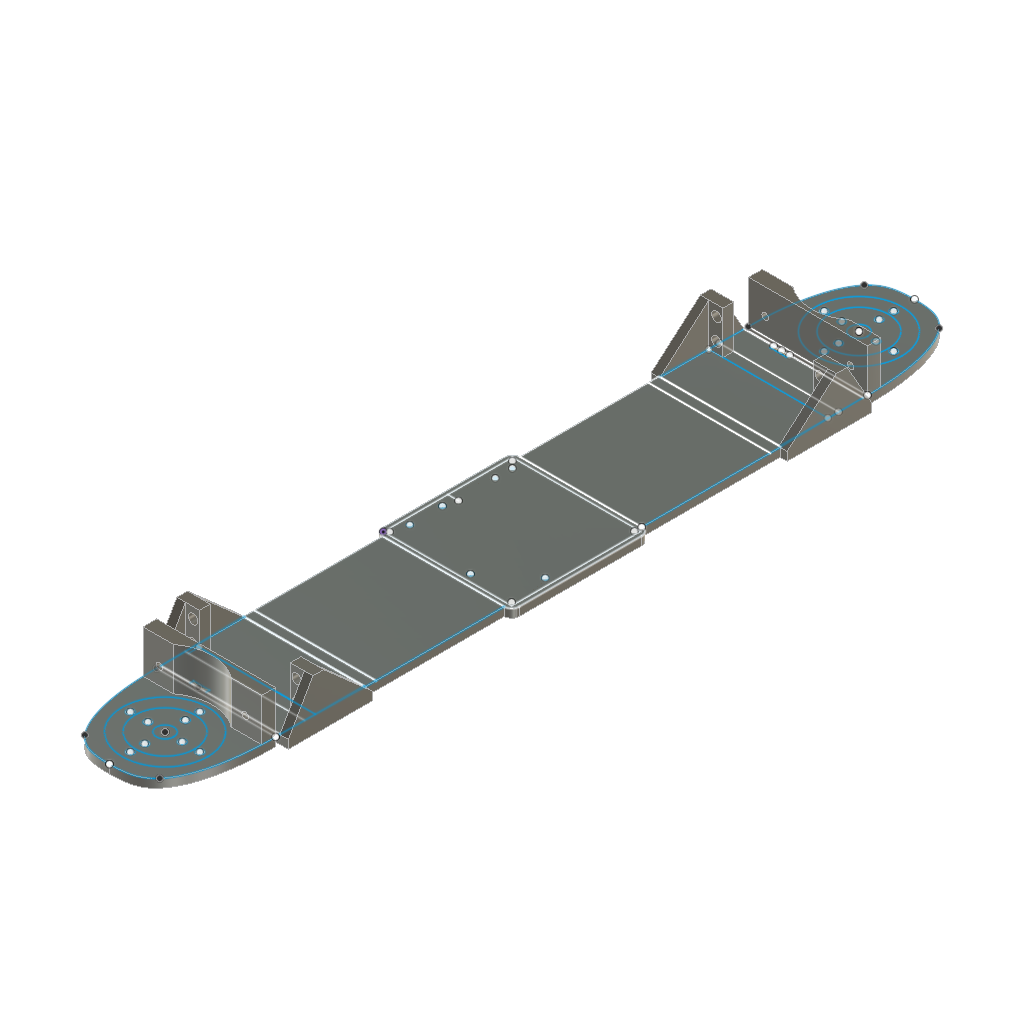
Aircraft Skeleton (Autodesk Fusion 360 design; units mm, degrees)
Autodesk Fusion 360 part; units mm, degrees
sketch "Sketch1" plane through (0, 0, 0) normal (0, 0, 1) x (1, 0, 0)
  line L0 (0, 0) -> (60, 0)
  line L1 (60, 0) -> (60, 60.328)
  line L2 (60, 60.328) -> (0, 60.328)
  line L3 (0, 60.328) -> (0, 0)
  circle A0 centre (4.445, 55.8804) radius 0.5
  circle A1 centre (4.445, 47.8804) radius 0.5
  circle A2 centre (3.398, 9) radius 1
  circle A3 centre (3.398, 24.24) radius 1
  circle A4 centre (37.45, 3.305) radius 1
  circle A5 centre (56.5, 19.18) radius 1
  line L4 (58.5, 62.328) -> (1.5, 62.328)
  line L5 (-2, 58.828) -> (-2, 1.5)
  line L6 (1.5, -2) -> (58.5, -2)
  line L7 (62, 1.5) -> (62, 58.828)
  arc A6 (1.5, 62.328) -> (-2, 58.828) centre (1.5, 58.828) ccw
  arc A7 (62, 58.828) -> (58.5, 62.328) centre (58.5, 58.828) ccw
  arc A8 (58.5, -2) -> (62, 1.5) centre (58.5, 1.5) ccw
  arc A9 (-2, 1.5) -> (1.5, -2) centre (1.5, 1.5) ccw
  line L8 (1.5, -2) -> (58.5, -2)
  line L9 (58.5, -2) -> (58.5, -62)
  line L10 (58.5, -62) -> (1.5, -62)
  line L11 (1.5, -62) -> (1.5, -2)
  line L12 (1.5, -62) -> (58.5, -62)
  line L13 (58.5, -62) -> (58.5, -67)
  line L14 (58.5, -67) -> (1.5, -67)
  line L15 (1.5, -67) -> (1.5, -62)
  line L16 (1.5, -67) -> (58.5, -67)
  line L17 (57.8, -106.2) -> (2.2, -106.2)
  line L18 (57.8, -94.7) -> (2.2, -94.7)
  line L19 (57.8, -67) -> (2.2, -67)
  line L20 (2.2, -67) -> (2.2, -106.2)
  line L21 (2.2, -106.2) -> (57.8, -106.2)
  line L22 (57.8, -106.2) -> (57.8, -67)
  line L23 (57.8, -106.2) -> (58.5, -67)
  line L24 (1.5, -67) -> (2.2, -106.2)
  line L25 (2.2, -108.2) -> (57.8, -108.2)
  circle A10 centre (30, -132.05) radius 13.85
  circle A11 centre (30, -122.55) radius 1.5
  circle A12 centre (38, -132.05) radius 1.5
  circle A13 centre (22, -132.05) radius 1.5
  circle A14 centre (30, -141.55) radius 1.5
  circle A15 centre (30, -132.05) radius 4
  circle A16 centre (30, -115.8) radius 1.5
  circle A17 centre (30, -148.3) radius 1.5
  circle A18 centre (13.75, -132.05) radius 1.5
  circle A19 centre (46.25, -132.05) radius 1.5
  circle A20 centre (30, -132.05) radius 20
  spline S0 degree 5 poles (2.2, -108.2) (2.2, -110.2358) (2.2593, -114.2119) (2.526, -119.8896) (3.2303, -126.8958) (4.6648, -134.7271) (6.6317, -141.619) (9.1298, -147.4803) (12.1699, -152.1961) (15.8043, -155.4644) (20.0344, -157.2387) (23.8195, -157.8281) (26.8436, -158.0092) (28.9353, -158.0498) (30, -158.05) knots 0 0 0 0 0 0 0.1 0.2 0.3 0.4 0.5 0.6 0.7 0.8 0.9 1 1 1 1 1 1
  line L26 (22.2675, -158.0488) -> (37.7325, -158.0512)
  line L27 (9, -148) -> (16, -156.1)
  line L28 (2.2, -98.7565) -> (2.2, -117.6435)
  spline S1 degree 5 poles (57.8, -108.2) (57.8, -110.2358) (57.7407, -114.2119) (57.474, -119.8896) (56.7697, -126.8958) (55.3352, -134.7271) (53.3683, -141.619) (50.8702, -147.4803) (47.8301, -152.1961) (44.1957, -155.4644) (39.9656, -157.2387) (36.1805, -157.8281) (33.1564, -158.0092) (31.0647, -158.0498) (30, -158.05) knots 0 0 0 0 0 0 0.1 0.2 0.3 0.4 0.5 0.6 0.7 0.8 0.9 1 1 1 1 1 1
  line L29 (57.8, -98.7565) -> (57.8, -117.6435)
  line L30 (51, -148) -> (44, -156.1)
  line L31 (37.7325, -158.0488) -> (22.2675, -158.0512)
  line L32 (2.2, -106.2) -> (19.7, -106.2)
  line L33 (23.45, -104.7) -> (15.95, -104.7)
  line L34 (15.95, -104.7) -> (15.95, -106.2)
  line L35 (23.45, -106.2) -> (23.45, -104.7)
  line L36 (23.45, -104.7) -> (19.7, -106.2) construction
  line L37 (15.95, -104.7) -> (19.7, -106.2) construction
  line L38 (0, 30.164) -> (5, 30.164)
  line L39 (1.5, 62.328) -> (58.5, 62.328)
  line L40 (58.5, 122.328) -> (1.5, 122.328)
  line L41 (1.5, 122.328) -> (58.5, 122.328)
  line L42 (58.5, 62.328) -> (58.5, 122.328)
  line L43 (57.8, 127.328) -> (2.2, 127.328)
  line L44 (23.45, 166.528) -> (23.45, 165.028)
  line L45 (15.95, 165.028) -> (19.7, 166.528) construction
  line L46 (2.2, 166.528) -> (57.8, 166.528)
  line L47 (57.8, 166.528) -> (2.2, 166.528)
  line L48 (15.95, 165.028) -> (15.95, 166.528)
  line L49 (23.45, 165.028) -> (19.7, 166.528) construction
  line L50 (23.45, 165.028) -> (15.95, 165.028)
  line L51 (2.2, 166.528) -> (19.7, 166.528)
  line L52 (57.8, 155.028) -> (2.2, 155.028)
  circle A21 centre (38, 192.378) radius 1.5
  circle A22 centre (46.25, 192.378) radius 1.5
  circle A23 centre (22, 192.378) radius 1.5
  circle A24 centre (13.75, 192.378) radius 1.5
  spline S2 degree 5 poles (2.2, 168.528) (2.2, 170.5638) (2.2593, 174.5399) (2.526, 180.2176) (3.2303, 187.2238) (4.6648, 195.0551) (6.6317, 201.947) (9.1298, 207.8083) (12.1699, 212.5241) (15.8043, 215.7924) (20.0344, 217.5667) (23.8195, 218.1561) (26.8436, 218.3372) (28.9353, 218.3778) (30, 218.378) knots 0 0 0 0 0 0 0.1 0.2 0.3 0.4 0.5 0.6 0.7 0.8 0.9 1 1 1 1 1 1
  line L53 (2.2, 159.0845) -> (2.2, 177.9715)
  line L54 (9, 208.328) -> (16, 216.428)
  line L55 (22.2675, 218.3768) -> (37.7325, 218.3792)
  circle A25 centre (30, 192.378) radius 13.85
  line L56 (2.2, 168.528) -> (57.8, 168.528)
  circle A26 centre (30, 201.878) radius 1.5
  circle A27 centre (30, 192.378) radius 20
  circle A28 centre (30, 208.628) radius 1.5
  spline S3 degree 5 poles (57.8, 168.528) (57.8, 170.5638) (57.7407, 174.5399) (57.474, 180.2176) (56.7697, 187.2238) (55.3352, 195.0551) (53.3683, 201.947) (50.8702, 207.8083) (47.8301, 212.5241) (44.1957, 215.7924) (39.9656, 217.5667) (36.1805, 218.1561) (33.1564, 218.3372) (31.0647, 218.3778) (30, 218.378) knots 0 0 0 0 0 0 0.1 0.2 0.3 0.4 0.5 0.6 0.7 0.8 0.9 1 1 1 1 1 1
  line L57 (57.8, 159.0845) -> (57.8, 177.9715)
  line L58 (51, 208.328) -> (44, 216.428)
  line L59 (37.7325, 218.3768) -> (22.2675, 218.3792)
  circle A29 centre (30, 182.878) radius 1.5
  circle A30 centre (30, 192.378) radius 4
  line L60 (1.5, 127.328) -> (1.5, 122.328)
  line L61 (1.5, 127.328) -> (58.5, 127.328)
  line L62 (58.5, 122.328) -> (58.5, 127.328)
  line L63 (1.5, 122.328) -> (1.5, 62.328)
  line L64 (58.5, 127.328) -> (1.5, 127.328)
  circle A31 centre (30, 176.128) radius 1.5
  line L65 (57.8, 166.528) -> (57.8, 127.328)
  line L66 (1.5, 127.328) -> (2.2, 166.528)
  line L67 (2.2, 127.328) -> (2.2, 166.528)
  line L68 (57.8, 166.528) -> (58.5, 127.328)
  line L69 (3.6, -94.7) -> (3.6, -89.7)
  line L70 (2.2, -89.7) -> (57.8, -89.7)
  line L71 (57.8, -89.7) -> (57.8, -89.7)
  line L72 (57.8, -89.7) -> (2.2, -89.7)
  line L73 (2.2, -89.7) -> (2.2, -89.7)
  line L74 (2.2, 150.028) -> (57.8, 150.028)
  point P0 (30, -132.05)
  point P1 (30, -132.05)
  point P2 (30, -132.05)
  point P3 (30, -132.05)
  point P4 (12.5, -152.05)
  point P5 (47.5, -152.05)
  point P6 (19.7, -106.2)
  point P7 (47.5, 212.378)
  point P8 (30, 192.378)
  point P9 (30, 192.378)
  point P10 (30, 192.378)
  point P11 (30, 192.378)
  point P12 (19.7, 166.528)
  point P13 (12.5, 212.378)
  dimension "d1" = 60
  dimension "d2" = 60.328
  dimension "d5" = 1
  dimension "d6" = 8
  dimension "d7" = 1
  dimension "d10" = 2
  dimension "d11" = 15.24
  dimension "d12" = 2
  dimension "d15" = 2
  dimension "d18" = 2
  dimension "d20" = 2
  dimension "d21" = 2
  dimension "d22" = 2
  dimension "d23" = 2
  dimension "d24" = 3.5
  dimension "d25" = 60
  dimension "d26" = 5
  dimension "d29" = 55.6
  dimension "d30" = 39.2
  dimension "d31" = 11.5
  dimension "d32" = 27.7
  dimension "d33" = 2
  dimension "d36" = 16
  dimension "d37" = 19
  dimension "d38" = 3
  dimension "d39" = 3
  dimension "d40" = 3
  dimension "d41" = 3
  dimension "d42" = 8
  dimension "d43" = 32.5
  dimension "d44" = 3
  dimension "d45" = 3
  dimension "d46" = 32.5
  dimension "d47" = 3
  dimension "d48" = 3
  dimension "d49" = 40
  dimension "d52" = 17.5
  dimension "d59" = 5
  constraint horizontal L0
  constraint vertical L1
  constraint horizontal L2
  constraint vertical L3
  constraint coincident L0.start L3.end
  constraint tangent L4 A6
  constraint tangent L5 A6
  constraint tangent L4 A7
  constraint tangent L7 A7
  constraint equal A6 A7
  constraint tangent L6 A8
  constraint tangent L7 A8
  constraint equal A6 A8
  constraint tangent L5 A9
  constraint tangent L6 A9
  constraint equal A6 A9
  constraint horizontal L8
  constraint vertical L9
  constraint horizontal L10
  constraint vertical L11
  constraint horizontal L12
  constraint vertical L13
  constraint horizontal L14
  constraint vertical L15
  constraint horizontal L16
  constraint horizontal L17
  constraint horizontal L19
  constraint perpendicular L19 L20
  constraint parallel L19 L21
  constraint parallel L20 L22
  constraint coincident L22 L18.start
  constraint coincident L20 L18.end
  constraint coincident P3 P2
  constraint concentric A10 A15
  constraint midpoint S0.end L26
  constraint midpoint P4 L27
  constraint midpoint L25.start L28
  constraint perpendicular L20 L32
  constraint horizontal L33
  constraint perpendicular L33 L34
  constraint parallel L34 L35
  constraint coincident L36 P6
  constraint coincident L37 P6
  constraint coincident P6 L32.end
  constraint coincident L17 L34.end
  constraint coincident L17 L35.start
  constraint midpoint L3 L38.start
  constraint perpendicular L3 L38
  constraint symmetric L6.end L38 L4.start
  constraint symmetric L6.start L38 L4.end
  constraint symmetric L9.end L38 L40.start
  constraint symmetric L10.end L38 L40.end
  constraint symmetric L13.end L38 L61.end
  constraint symmetric L14.end L38 L60.start
  constraint symmetric L19.start L38 L43.start
  constraint symmetric L19.end L38 L43.end
  constraint symmetric L17.end L38 L46.start
  constraint symmetric L17.start L38 L46.end
  constraint symmetric L18.start L38 L52.start
  constraint symmetric L18.end L38 L52.end
  constraint symmetric L25.start L38 S2.start
  constraint symmetric L25.end L38 L56.end
  constraint symmetric A10 L38 A25
  constraint symmetric P3 L38 P11
  constraint symmetric A11 L38 A29
  constraint symmetric A12 L38 A21
  constraint symmetric A13 L38 A23
  constraint symmetric A14 L38 A26
  constraint symmetric A15 L38 A30
  constraint symmetric A16 L38 A31
  constraint symmetric A17 L38 A28
  constraint symmetric A18 L38 A24
  constraint symmetric A19 L38 A22
  constraint symmetric A20 L38 A27
  constraint symmetric P4 L38 P13
  constraint symmetric S0.end L38 S2.end
  constraint symmetric L26.start L38 L55.start
  constraint symmetric L26.end L38 L55.end
  constraint symmetric L27.start L38 L54.start
  constraint symmetric L27.end L38 L54.end
  constraint symmetric L28.start L38 L53.start
  constraint symmetric L28.end L38 L53.end
  constraint symmetric P5 L38 P7
  constraint symmetric L29.start L38 L57.start
  constraint symmetric L29.end L38 L57.end
  constraint symmetric L30.start L38 L58.start
  constraint symmetric L30.end L38 L58.end
  constraint symmetric L31.start L38 L59.start
  constraint symmetric L31.end L38 L59.end
  constraint symmetric P6 L38 P12
  constraint symmetric L33.start L38 L44.end
  constraint symmetric L33.end L38 L45.start
  constraint symmetric L34.end L38 L48.end
  constraint symmetric L35.start L38 L44.start
  constraint coincident L18 L69.start
  constraint perpendicular L18 L69
  constraint horizontal L70
  constraint horizontal L72
  constraint coincident L22 L70.end
  constraint coincident L20 L70.start
  constraint symmetric L38 L70.start L74.start
  constraint symmetric L38 L70.end L74.end
  measures "d1" distance of L0.start L0.end
  measures "d2" distance of L0.start L2.end
  measures "d5" diameter of A0
  measures "d6" distance of A0.centre A1.centre
  measures "d7" diameter of A1
  measures "d10" diameter of A2
  measures "d11" distance of A2.centre A3.centre
  measures "d12" diameter of A3
  measures "d15" diameter of A4
  measures "d18" diameter of A5
  measures "d20" distance of L2 L4
  measures "d21" distance of L3 L5
  measures "d22" distance of L0 L6
  measures "d23" distance of L1 L7
  measures "d24" radius of A6
  measures "d25" distance of L6.start L10.end
  measures "d26" distance of L10.end L14.end
  measures "d29" distance of L17.end L17.start
  measures "d30" distance of L19.end L17.end
  measures "d31" distance of L17 L18
  measures "d32" distance of L16 L18
  measures "d36" distance of A12.centre A13.centre
  measures "d37" distance of A11.centre A14.centre
  measures "d38" diameter of A11
  measures "d39" diameter of A12
  measures "d40" diameter of A13
  measures "d41" diameter of A14
  measures "d42" diameter of A15
  measures "d43" distance of A16.centre A17.centre
  measures "d44" diameter of A16
  measures "d45" diameter of A17
  measures "d46" distance of A18.centre A19.centre
  measures "d47" diameter of A18
  measures "d48" diameter of A19
  measures "d49" diameter of A20
  measures "d52" distance of L17.end P6
  measures "d59" distance of L69.start L69.end
extrude "Extrude1" add sketch "Sketch1" against normal blind 4 contours L0 L1 L2 L3 | A0 | A1 | A2 | A3 | A4 | A5 | L4 L5 L6 L7 A6 A7 A8 A9 L8 L39 | L4 L39 L40 L41 L42 L63 | L40 L41 L43 L60 L61 L62 L64 | L57 L61 L64 L65 L68 | L53 L61 L64 L66 L67 | L6 L8 L9 L10 L11 L12 | L43 L61 L64 L65 L67 L74 | L44 L46 L47 L48 L50 L51 L52 L53 L57 L65 L67 | L10 L12 L13 L14 L15 L16 L19 | L52 L65 L67 L74 | L44 L46 L47 L48 L50 L51 | S2 L56 S3 | L14 L16 L22 L23 L29 | L14 L16 L20 L24 L28 | L14 L16 L19 L20 L22 L70 L72 | L17 L18 L20 L21 L22 L28 L29 L32 L33 L34 L35 | L18 L22 L69 L70 L72 | L17 L21 L32 L33 L34 L35 | L25 S0 S1 | L18 L20 L69 L70 L72 | A10 | A11 | A12 | A13 | A14 | A15 | A16 | A17 | A18 | A19 | A20 | A21 | A22 | A23 | A24 | A25 | A26 | A27 | A28 | A29 | A30 | A31 makes body 1 at (38.8701, 174.7326, 0) makes body 2 at (38.8701, -114.4046, 0) makes body 3 at (20.5, -43.6667, 0)
extrude "Extrude2" cut sketch "Sketch1" against normal blind 13 contours A2 | A3 | A4 | A5 | A11 | A12 | A13 | A14 | A16 | A17 | A18 | A19 | A21 | A22 | A23 | A24 | A26 | A28 | A29 | A31 bodies 1 2 3
extrude "Extrude3" add sketch "Sketch1" along normal blind 20 contours L52 L65 L67 L74 | L18 L22 L69 L70 L72 | L18 L20 L69 L70 L72 bodies 3
sketch "Sketch2" plane through (0, -94.7, 0) normal (0, -1, 0) x (1, 0, 0)
  line L0 (2.2, 0) -> (57.8, 0)
  line L1 (57.8, 0) -> (57.8, 20)
  line L2 (57.8, 20) -> (2.2, 20)
  line L3 (2.2, 20) -> (2.2, 0)
  line L4 (54.25, 20) -> (5.75, 20)
  circle A0 centre (5.75, 15) radius 2.25
  circle A1 centre (5.75, 5) radius 2.25
  line L5 (30, 20) -> (30, 19.5)
  circle A2 centre (54.25, 15) radius 2.25
  circle A3 centre (54.25, 5) radius 2.25
  line L6 (51.25, 20) -> (8.75, 20)
  line L7 (8.75, 20) -> (8.75, 0)
  line L8 (51.25, 20) -> (51.25, 0)
  line L9 (8.75, 0) -> (51.25, 0)
  point P0 (30, 20)
  point P1 (5.75, 10)
  dimension "d62" = 48.5
  dimension "d65" = 10
  dimension "d66" = 4.5
  dimension "d67" = 4.5
  dimension "d68" = 42.5
  constraint midpoint L4 P0
  constraint coincident L2 P0
  constraint parallel L2 L4
  constraint coincident P0 L5.start
  constraint perpendicular L4 L5
  constraint symmetric A0 L5 A2
  constraint symmetric A1 L5 A3
  constraint midpoint P0 L6
  constraint coincident L4 L6.end
  constraint coincident L0 L7.end
  constraint perpendicular L0 L7
  constraint coincident L0 L8.end
  constraint perpendicular L0 L8
  measures "d62" distance of L4.start L4.end
  measures "d65" distance of A0.centre A1.centre
  measures "d66" diameter of A0
  measures "d67" diameter of A1
  measures "d68" distance of L6.start L6.end
extrude "Extrude4" cut sketch "Sketch2" against normal blind 350 contours L0 L2 L4 L6 L7 L8 L9 | A0 | A1 | A2 | A3 bodies 3
sketch "Sketch3" plane through (2.2, 0, 0) normal (-1, 0, 0) x (0, -1, 0)
  line L0 (89.7, 0) -> (94.7, 0)
  line L1 (94.7, 0) -> (94.7, 20)
  line L2 (94.7, 20) -> (89.7, 20)
  line L3 (89.7, 20) -> (89.7, 0)
  line L4 (89.7, 20) -> (67, 0)
  line L5 (67, 0) -> (67, -4)
  line L6 (67, -4) -> (94.7, -4)
  line L7 (94.7, -4) -> (94.7, 20)
  line L8 (89.7, 20) -> (94.7, 20)
  line L9 (94.7, 20) -> (106.2, 0)
  line L10 (106.2, 0) -> (106.2, -4)
  line L11 (106.2, -4) -> (94.7, -4)
  constraint coincident L2.end L3.start
  constraint perpendicular L2 L5
  constraint perpendicular L1 L6
  constraint coincident L1.end L2.start
  constraint perpendicular L2 L7
  constraint perpendicular L8 L10
  constraint perpendicular L7 L11
extrude "Extrude5" add sketch "Sketch3" along normal blind 4 bodies 3
move_body "Move1" bodies 3 to x (1, 0, 0) y (0, 1, 0) z (0, 0, 1) at (-49.05, 0, 0)
move_body "Move2" bodies 3 to x (1, 0, 0) y (0, 1, 0) z (0, 0, 1) at (-6.55, 0, 0)
extrude "Extrude6" add sketch "Sketch3" against normal blind 4 bodies 3
move_body "Move3" bodies 3 to x (1, 0, 0) y (0, 1, 0) z (0, 0, 1) at (-10, 0, 0)
move_body "Move4" bodies 3 to x (1, 0, 0) y (0, 1, 0) z (0, 0, 1) at (65.6, 0, 0)
sketch "Sketch4" plane through (57.8, 0, 0) normal (1, 0, 0) x (0, 1, 0)
  line L0 (150.028, 0) -> (155.028, 0)
  line L1 (155.028, 0) -> (155.028, 20)
  line L2 (155.028, 20) -> (150.028, 20)
  line L3 (150.028, 20) -> (150.028, 0)
  line L4 (150.028, 20) -> (155.028, 20)
  line L5 (155.028, 20) -> (166.5, 0)
  line L6 (166.5, 0) -> (166.5, -4)
  line L7 (166.5, -4) -> (150.028, -4)
  line L8 (150.028, 20) -> (127, 0)
  line L9 (127, 0) -> (127, -4)
  line L10 (127, -4) -> (150.028, -4)
  constraint coincident L2.end L3.start
  constraint coincident L1.end L2.start
  constraint perpendicular L4 L6
  constraint perpendicular L6 L7
  constraint perpendicular L4 L9
  constraint perpendicular L9 L10
extrude "Extrude7" add sketch "Sketch4" along normal blind 4 bodies 3
move_body "Move5" bodies 3 to x (1, 0, 0) y (0, 1, 0) z (0, 0, 1) at (55.6, 0, 0)
extrude "Extrude8" add sketch "Sketch4" against normal blind 4 bodies 3
move_body "Move6" bodies 3 to x (1, 0, 0) y (0, 1, 0) z (0, 0, 1) at (-55.6, 0, 0)
sketch "Sketch5" plane through (0, 0, 0) normal (0, 0, 1) x (1, 0, 0)
  line L0 (2.2, 168.528) -> (57.8, 168.528)
  spline S0 degree 5 poles (57.8, 168.528) (57.8, 170.5638) (57.7407, 174.5399) (57.474, 180.2176) (56.7697, 187.2238) (55.3352, 195.0551) (53.3683, 201.947) (50.8702, 207.8083) (47.8301, 212.5241) (44.1957, 215.7924) (39.9656, 217.5667) (36.1805, 218.1561) (33.1564, 218.3372) (31.0647, 218.3778) (30, 218.378) knots 0 0 0 0 0 0 0.1 0.2 0.3 0.4 0.5 0.6 0.7 0.8 0.9 1 1 1 1 1 1
  spline S1 degree 5 poles (2.2, 168.528) (2.2, 170.5638) (2.2593, 174.5399) (2.526, 180.2176) (3.2303, 187.2238) (4.6648, 195.0551) (6.6317, 201.947) (9.1298, 207.8083) (12.1699, 212.5241) (15.8043, 215.7924) (20.0344, 217.5667) (23.8195, 218.1561) (26.8436, 218.3372) (28.9353, 218.3778) (30, 218.378) knots 0 0 0 0 0 0 0.1 0.2 0.3 0.4 0.5 0.6 0.7 0.8 0.9 1 1 1 1 1 1
  circle A0 centre (46.25, 192.378) radius 1.5
  circle A1 centre (30, 182.878) radius 1.5
  circle A2 centre (13.75, 192.378) radius 1.5
  circle A3 centre (30, 208.628) radius 1.5
  circle A4 centre (38, 192.378) radius 1.5
  circle A5 centre (22, 192.378) radius 1.5
  circle A6 centre (30, 176.128) radius 1.5
  circle A7 centre (30, 201.878) radius 1.5
  line L1 (22, 192.378) -> (38, 192.378)
  line L2 (30, 182.878) -> (30, 201.878)
  circle A8 centre (30, 192.378) radius 22
  line L3 (2.3242, 174.9243) -> (16.6071, 174.9243)
  line L4 (43.3929, 174.9243) -> (57.6758, 174.9243)
  dimension "d82" = 44
  constraint coincident A5.centre L1.start
  constraint coincident A4.centre L1.end
  constraint coincident A1.centre L2.start
  constraint coincident A7.centre L2.end
  constraint midpoint L2 A8.centre
  constraint coincident S1 L3.start
  constraint coincident A8 L3.end
  constraint horizontal L3
  constraint coincident A8 L4.start
  constraint coincident S0 L4.end
  constraint parallel L3 L4
  measures "d82" diameter of A8
extrude "Extrude9" add sketch "Sketch5" along normal blind 20 contours L0 S0 S1 A8 L3 L4 bodies 1
sketch "Sketch6" plane through (0, 168.528, 0) normal (0, -1, 0) x (1, 0, 0)
  line L0 (2.2, 0) -> (2.2, -4)
  line L1 (2.2, -4) -> (57.8, -4)
  line L2 (57.8, -4) -> (57.8, 0)
  line L3 (57.8, 0) -> (57.8, 20)
  line L4 (57.8, 20) -> (2.2, 20)
  line L5 (2.2, 20) -> (2.2, 0)
  line L6 (2.2, 20) -> (57.8, -4)
  line L7 (2.2, -4) -> (57.8, 20)
  line L8 (50, 8) -> (10, 8)
  circle A0 centre (10, 8) radius 1.5
  circle A1 centre (50, 8) radius 1.5
  point P0 (30, 8)
  dimension "d85" = 3
  dimension "d86" = 3
  constraint coincident L4.end L5.start
  constraint coincident L1.end L2.start
  constraint coincident L0.end L1.start
  constraint coincident L3.end L4.start
  constraint midpoint L8 P0
  constraint coincident L6 P0
  constraint parallel L4 L8
  constraint coincident L8.end A0.centre
  constraint coincident L8.start A1.centre
  measures "d85" diameter of A0
  measures "d86" diameter of A1
extrude "Extrude10" cut sketch "Sketch6" against normal blind 11 contours A0 | A1 bodies 1
sketch "Sketch7" plane through (0, 0, 0) normal (0, 0, 1) x (1, 0, 0)
  spline S0 degree 5 poles (2.2, -108.2) (2.2, -110.2358) (2.2593, -114.2119) (2.526, -119.8896) (3.2303, -126.8958) (4.6648, -134.7271) (6.6317, -141.619) (9.1298, -147.4803) (12.1699, -152.1961) (15.8043, -155.4644) (20.0344, -157.2387) (23.8195, -157.8281) (26.8436, -158.0092) (28.9353, -158.0498) (30, -158.05) knots 0 0 0 0 0 0 0.1 0.2 0.3 0.4 0.5 0.6 0.7 0.8 0.9 1 1 1 1 1 1
  spline S1 degree 5 poles (57.8, -108.2) (57.8, -110.2358) (57.7407, -114.2119) (57.474, -119.8896) (56.7697, -126.8958) (55.3352, -134.7271) (53.3683, -141.619) (50.8702, -147.4803) (47.8301, -152.1961) (44.1957, -155.4644) (39.9656, -157.2387) (36.1805, -157.8281) (33.1564, -158.0092) (31.0647, -158.0498) (30, -158.05) knots 0 0 0 0 0 0 0.1 0.2 0.3 0.4 0.5 0.6 0.7 0.8 0.9 1 1 1 1 1 1
  line L0 (57.8, -108.2) -> (2.2, -108.2)
  circle A0 centre (46.25, -132.05) radius 1.5
  circle A1 centre (22, -132.05) radius 1.5
  circle A2 centre (30, -148.3) radius 1.5
  circle A3 centre (30, -115.8) radius 1.5
  circle A4 centre (38, -132.05) radius 1.5
  circle A5 centre (13.75, -132.05) radius 1.5
  circle A6 centre (30, -141.55) radius 1.5
  circle A7 centre (30, -122.55) radius 1.5
  circle A8 centre (30, -132) radius 22
  line L1 (2.3242, -114.596) -> (16.5426, -114.596)
  line L2 (43.4574, -114.596) -> (57.6758, -114.596)
  line L3 (2.2, -108.2) -> (57.8, -108.2)
  dimension "d89" = 44
  dimension "d90" = 6.396
  dimension "d91" = 6.396
  constraint coincident S0 L1.start
  constraint coincident A8 L1.end
  constraint horizontal L1
  constraint coincident A8 L2.start
  constraint coincident S1 L2.end
  constraint parallel L1 L2
  measures "d89" diameter of A8
  measures "d90" distance of L1 L3
  measures "d91" distance of L2 L3
extrude "Extrude11" add sketch "Sketch7" along normal blind 20 contours S0 S1 L0 A8 L1 L2 L3 bodies 2
sketch "Sketch8" plane through (0, -108.2, 0) normal (0, 1, 0) x (-1, 0, 0)
  line L0 (-57.8, 0) -> (-57.8, -4)
  line L1 (-57.8, -4) -> (-2.2, -4)
  line L2 (-2.2, -4) -> (-2.2, 0)
  line L3 (-2.2, 0) -> (-2.2, 20)
  line L4 (-2.2, 20) -> (-57.8, 20)
  line L5 (-57.8, 20) -> (-57.8, 0)
  line L6 (-57.8, -4) -> (-2.2, 20)
  line L7 (-2.2, -4) -> (-57.8, 20)
  line L8 (-10, 8) -> (-50, 8)
  circle A0 centre (-50, 8) radius 1.5
  circle A1 centre (-10, 8) radius 1.5
  point P0 (-30, 8)
  dimension "d94" = 40
  dimension "d95" = 3
  dimension "d96" = 3
  constraint coincident L0.end L1.start
  constraint coincident L3.end L4.start
  constraint coincident L1.end L2.start
  constraint coincident L4.end L5.start
  constraint midpoint L8 P0
  constraint coincident L7 P0
  constraint horizontal L8
  constraint coincident L8.end A0.centre
  constraint coincident L8.start A1.centre
  measures "d94" distance of L8.start L8.end
  measures "d95" diameter of A0
  measures "d96" diameter of A1
extrude "Extrude12" cut sketch "Sketch8" against normal blind 12 contours A0 | A1 bodies 2
